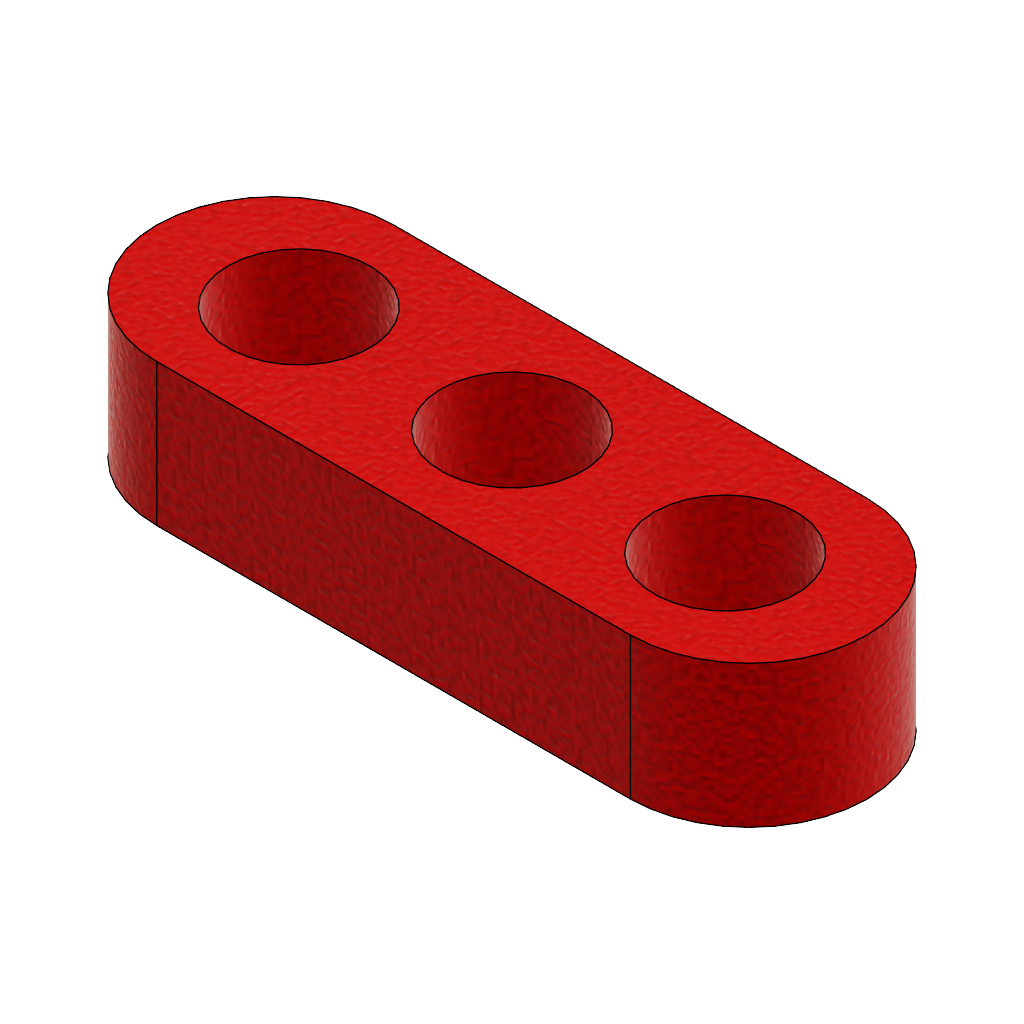
level -2 task 1 replicate structure (Autodesk Fusion 360 design; units mm, degrees)
part number: 2026-10-11-14-07-19-786
Autodesk Fusion 360 part; units mm, degrees
sketch "Sketch10" plane through (0, 0, 0) normal (0, 1, 0) x (1, 0, 0)
sketch "Sketch11" plane through (0, 0, 0) normal (0, 1, 0) x (1, 0, 0)
  line L0 (30, 10) -> (-30, 10)
  line L1 (-30, 10) -> (-30, -10)
  line L2 (-30, -10) -> (30, -10)
  line L3 (30, -10) -> (30, 10)
  line L4 (30, 10) -> (-30, -10) construction
  line L5 (-30, 10) -> (30, -10) construction
  circle A0 centre (0, 0) radius 6
  circle A1 centre (18, 0) radius 6
  circle A2 centre (-18, 0) radius 6
  dimension "d48" = 60
  dimension "d49" = 20
  dimension "d50" = 12
  dimension "d51" = 12
  dimension "d52" = 12
  constraint horizontal L0
  constraint perpendicular L0 L1
  constraint parallel L0 L2
  constraint parallel L1 L3
  constraint coincident L4 A0.centre
  constraint coincident L5 A0.centre
  constraint coincident A0.centre origin
  measures "d48" distance of L1.end L2.end
  measures "d49" distance of L0.end L1.end
  measures "d50" diameter of A0
  measures "d51" diameter of A1
  measures "d52" diameter of A2
extrude "Extrude5" add sketch "Sketch11" along normal blind 12
fillet "Fillet2" radius 10 4 edges at (30, 6, 10) (30, 6, -10) (-30, 6, 10) (-30, 6, -10)
